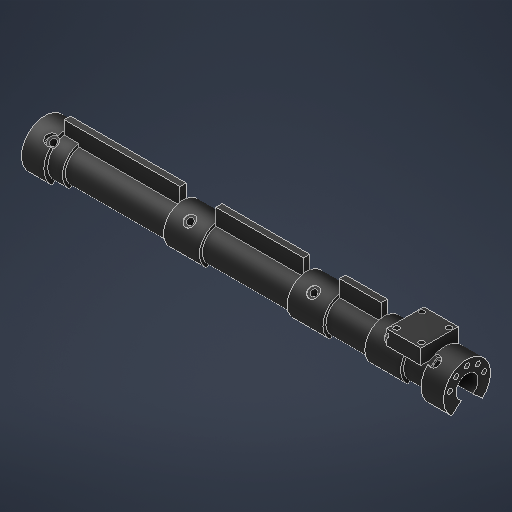
# Autodesk Inventor part: s1101mfd1006
Saved by Autodesk Inventor 2027.1 (Build 311270010, 270A)
## iProperties
Created: 2026-10-31
Part Number: s1101mfd1006
Material: Generic
Document SubType Name: Modeling
Designer: User
Density: 1 g/cm^3
Appearance: Anodized - Dark Gray
Author: User
Autodesk Inventor part; units mm, degrees
sketch "Sketch1" plane through (0, 0, 0) normal (0, 0, 1) x (1, 0, 0)
  line L0 (0, 11.2522) -> (429.9966, 11.2522)
  line L1 (429.9966, 11.2522) -> (429.9966, 24.003)
  line L2 (429.9966, 24.003) -> (407.1366, 24.003)
  line L3 (407.1366, 24.003) -> (407.1366, 16.9926)
  line L4 (407.1366, 16.9926) -> (382.27, 16.9926)
  line L5 (382.27, 16.9926) -> (382.27, 19.9898)
  line L6 (382.27, 19.9898) -> (345.7448, 19.9898)
  line L7 (345.7448, 19.9898) -> (345.7448, 16.9926)
  line L8 (345.7448, 16.9926) -> (303.149, 16.9926)
  line L9 (303.149, 16.9926) -> (303.149, 19.9898)
  line L10 (303.149, 19.9898) -> (266.6238, 19.9898)
  line L11 (266.6238, 19.9898) -> (266.6238, 16.9926)
  line L12 (266.6238, 16.9926) -> (177.2666, 16.9926)
  line L13 (177.2666, 16.9926) -> (177.2666, 19.9898)
  line L14 (177.2666, 19.9898) -> (140.7414, 19.9898)
  line L15 (140.7414, 19.9898) -> (140.7414, 16.9926)
  line L16 (140.7414, 16.9926) -> (37.7698, 16.9926)
  line L17 (37.7698, 16.9926) -> (37.7698, 19.9898)
  line L18 (37.7698, 19.9898) -> (22.86, 19.9898)
  line L19 (22.86, 19.9898) -> (22.86, 24.003)
  line L20 (22.86, 24.003) -> (0, 24.003)
  line L21 (0, 24.003) -> (0, 11.2522)
  line L22 (0, 0) -> (429.9966, 0) construction
  constraints: 46 end point
revolve "Revolution1" add sketch "Sketch1" angle 360 about axis through (0, 0, 0) along (1, 0, 0)
sketch "Sketch2" plane through (0, 0, 0) normal (1, 0, 0) x (0, 1, 0)
  line L0 (-9.5225, -5.9944) -> (-26.67, -25.0387)
  line L1 (-26.67, -25.0387) -> (-26.67, 25.0387)
  line L2 (-26.67, 25.0387) -> (-9.5225, 5.9944)
  line L3 (-9.5225, 5.9944) -> (-9.5225, -5.9944)
  constraints: 8 end point
extrude "Extrusion1" cut sketch "Sketch2" along normal through all both and the other way through all
sketch "Sketch3" plane through (0, 0, 0) normal (0, 0, 1) x (1, 0, 0)
  line L0 (22.86, 15.24) -> (140.7414, 15.24)
  line L1 (140.7414, 15.24) -> (140.7414, 33.3502)
  line L2 (140.7414, 33.3502) -> (22.86, 33.3502)
  line L3 (22.86, 33.3502) -> (22.86, 15.24)
  line L4 (177.2666, 15.24) -> (266.6238, 15.24)
  line L5 (266.6238, 15.24) -> (266.6238, 33.3502)
  line L6 (266.6238, 33.3502) -> (177.2666, 33.3502)
  line L7 (177.2666, 33.3502) -> (177.2666, 15.24)
  line L8 (303.149, 15.24) -> (345.7448, 15.24)
  line L9 (345.7448, 15.24) -> (345.7448, 33.3502)
  line L10 (345.7448, 33.3502) -> (303.149, 33.3502)
  line L11 (303.149, 33.3502) -> (303.149, 15.24)
  constraints: 24 end point, 6 parallel, 3 horizontal, 3 perpendicular
extrude "Extrusion2" add sketch "Sketch3" along normal mid plane 6.35
ref_plane "Work Plane1" through (0, 21.59, 0) normal (0, -1, 0) x (1, 0, 0)
sketch "Sketch4" plane through (0, 21.59, 0) normal (0, -1, 0) x (1, 0, 0)
  line L0 (367.03, -19.05) -> (401.955, -19.05)
  line L1 (401.955, -19.05) -> (401.955, 19.05)
  line L2 (401.955, 19.05) -> (367.03, 19.05)
  line L3 (367.03, 19.05) -> (367.03, -19.05)
  constraints: 8 end point, 2 parallel, 1 horizontal, 1 perpendicular
extrude "Extrusion3" add sketch "Sketch4" along normal mid plane 15.24
ref_plane "Work Plane2" through (0, 24.13, 0) normal (0, -1, 0) x (1, 0, 0)
sketch "Sketch5" plane through (0, 24.13, 0) normal (0, -1, 0) x (1, 0, 0)
  circle A0 centre (370.205, -13.5001) radius 2.7686
  circle A1 centre (371.8052, 13.5001) radius 2.7686
  circle A2 centre (397.2052, 13.5001) radius 2.7686
  circle A3 centre (398.145, -13.5001) radius 2.7686
  constraints: 4 centre point
extrude "Extrusion4" cut sketch "Sketch5" along normal mid plane 12.7
ref_plane "Work Plane3" through (0, 0, 0) normal (1, 0, 0) x (0, 1, 0)
sketch "Sketch6" plane through (0, 0, 0) normal (1, 0, 0) x (0, 1, 0)
  circle A0 centre (4.3567, -17.4737) radius 2.4892
  circle A1 centre (14.191, -11.0872) radius 2.4892
  circle A2 centre (18.0086, 0) radius 2.4892
  circle A3 centre (14.191, 11.0872) radius 2.4892
  circle A4 centre (4.3567, 17.4737) radius 2.4892
  constraints: 5 centre point
extrude "Extrusion5" cut sketch "Sketch6" along normal blind 13.97
ref_plane "Work Plane4" through (429.9966, 0, 0) normal (1, 0, 0) x (0, 1, 0)
sketch "Sketch7" plane through (429.9966, 0, 0) normal (1, 0, 0) x (0, 1, 0)
  circle A0 centre (4.3567, -17.4737) radius 2.4892
  circle A1 centre (14.191, -11.0872) radius 2.4892
  circle A2 centre (18.0086, 0) radius 2.4892
  circle A3 centre (14.191, 11.0872) radius 2.4892
  circle A4 centre (4.3567, 17.4737) radius 2.4892
  constraints: 5 centre point
extrude "Extrusion6" cut sketch "Sketch7" against normal blind 13.97
ref_plane "Work Plane5" through (0, 20.8065, 14.5688) normal (0, -0.8192, -0.5736) x (1, 0, 0)
sketch "Sketch8" plane through (0, 20.8065, 14.5688) normal (0, -0.8192, -0.5736) x (1, 0, 0)
  circle A0 centre (19.5072, 0) radius 5.5499
  circle A1 centre (159.004, 0) radius 5.5499
  circle A2 centre (284.8864, 0) radius 5.5499
  circle A3 centre (364.0074, 0) radius 5.5499
  circle A4 centre (410.4894, 0) radius 5.5499
  constraints: 5 centre point
extrude "Extrusion7" cut sketch "Sketch8" along normal mid plane 12.7
ref_plane "Work Plane6" through (0, 13.5242, 9.4697) normal (0, -0.8192, -0.5736) x (1, 0, 0)
sketch "Sketch9" plane through (0, 13.5242, 9.4697) normal (0, -0.8192, -0.5736) x (1, 0, 0)
  circle A0 centre (19.5072, 0) radius 3.2258
  circle A1 centre (159.004, 0) radius 3.2258
  circle A2 centre (284.8864, 0) radius 3.2258
  circle A3 centre (364.0074, 0) radius 3.2258
  circle A4 centre (410.4894, 0) radius 3.2258
  constraints: 5 centre point
extrude "Extrusion8" cut sketch "Sketch9" along normal mid plane 12.7
body "Solid1"
